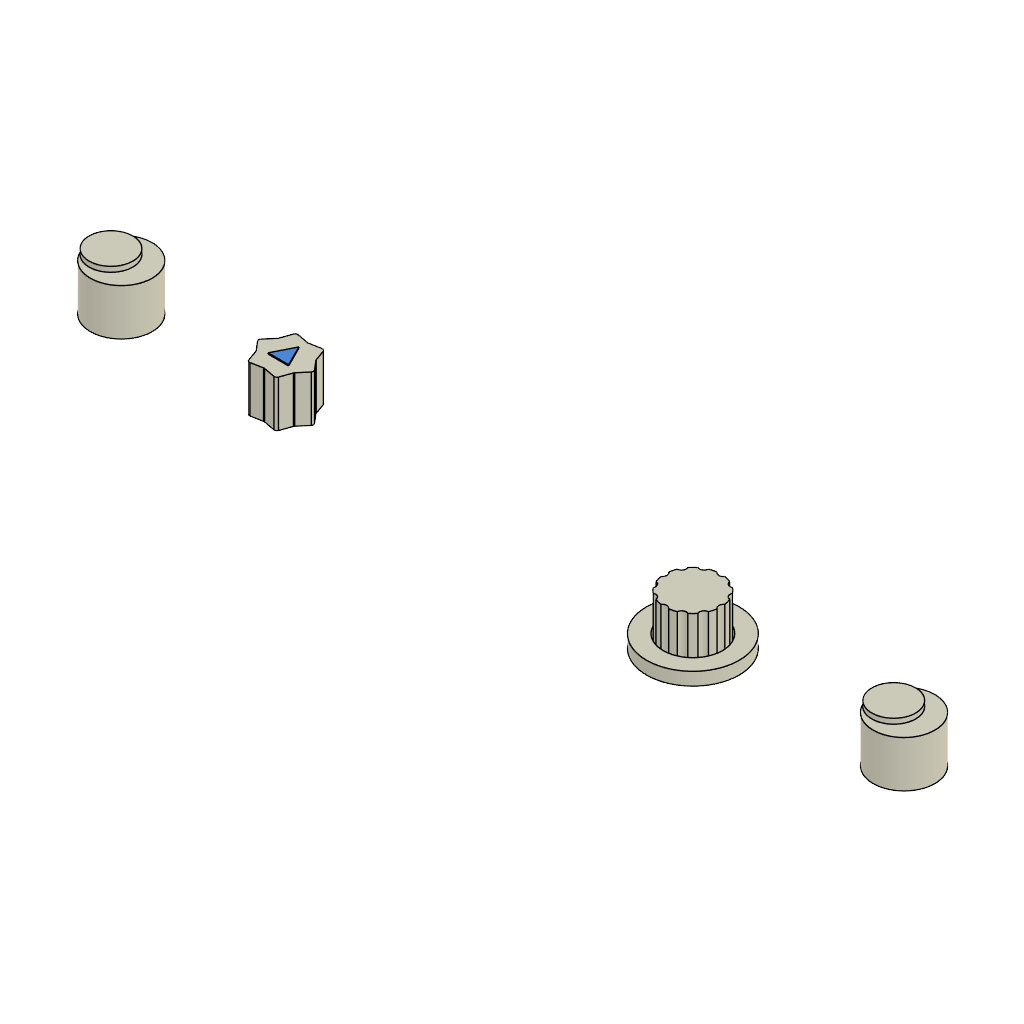
04-printable-fcu-knobs (Autodesk Fusion 360 design; units mm, degrees)
part number: 2026-10-09-16-49-26-165
Autodesk Fusion 360 part; units mm, degrees
ref_plane "WorkPlane1" through (0, 0, 5) normal (0, 0, 1) x (1, 0, 0)
sketch "SPEED knob footprint" plane through (0, 0, 5) normal (0, 0, 1) x (1, 0, 0)
  circle A0 centre (236, 66) radius 12
extrude "SPEED knob" add sketch "SPEED knob footprint" along normal blind 18 makes body 1
ref_plane "WorkPlane2" through (0, 0, 5) normal (0, 0, 1) x (1, 0, 0)
sketch "SPEED shaft socket" plane through (0, 0, 5) normal (0, 0, 1) x (1, 0, 0)
  circle A0 centre (236, 66) radius 3.1
  dimension "d1207" = 6.2
  measures "d1207" diameter of A0
extrude "SPEED shaft socket cut" cut sketch "SPEED shaft socket" along normal blind 14 bodies 1
ref_plane "WorkPlane3" through (0, 0, 23) normal (0, 0, 1) x (1, 0, 0)
sketch "SPEED crown footprint" plane through (0, 0, 23) normal (0, 0, 1) x (1, 0, 0)
  circle A0 centre (232, 66) radius 8.5
extrude "SPEED crown" add sketch "SPEED crown footprint" along normal blind 2 separate body makes body 2
combine "Combine1" operation add target body 1 tool bodies 2
ref_plane "WorkPlane4" through (0, 0, 5) normal (0, 0, 1) x (1, 0, 0)
sketch "Heading lobed knob" plane through (0, 0, 5) normal (0, 0, 1) x (1, 0, 0)
  line L0 (311, 66) -> (307.3612, 70.25)
  line L1 (307.3612, 70.25) -> (305.5, 75.5263)
  line L2 (305.5, 75.5263) -> (300, 74.5)
  line L3 (300, 74.5) -> (294.5, 75.5263)
  line L4 (294.5, 75.5263) -> (292.6388, 70.25)
  line L5 (292.6388, 70.25) -> (289, 66)
  line L6 (289, 66) -> (292.6388, 61.75)
  line L7 (292.6388, 61.75) -> (294.5, 56.4737)
  line L8 (294.5, 56.4737) -> (300, 57.5)
  line L9 (300, 57.5) -> (305.5, 56.4737)
  line L10 (305.5, 56.4737) -> (307.3612, 61.75)
  line L11 (307.3612, 61.75) -> (311, 66)
extrude "HEADING knob" add sketch "Heading lobed knob" along normal blind 18 separate body makes body 3
fillet "Fillet1" radius 1 12 edges at (307.3612, 61.75, 14) (305.5, 56.4737, 14) (300, 57.5, 14) (294.5, 56.4737, 14) (292.6388, 61.75, 14) (289, 66, 14) (292.6388, 70.25, 14) (294.5, 75.5263, 14) (300, 74.5, 14) (305.5, 75.5263, 14) (307.3612, 70.25, 14) (311, 66, 14) on bodies 3
ref_plane "WorkPlane5" through (0, 0, 5) normal (0, 0, 1) x (1, 0, 0)
sketch "HEADING shaft socket" plane through (0, 0, 5) normal (0, 0, 1) x (1, 0, 0)
  circle A0 centre (300, 66) radius 3.1
  dimension "d1222" = 6.2
  measures "d1222" diameter of A0
extrude "HEADING shaft socket cut" cut sketch "HEADING shaft socket" along normal blind 14 bodies 3
ref_plane "WorkPlane6" through (0, 0, 23) normal (0, 0, 1) x (1, 0, 0)
sketch "Heading triangular index" plane through (0, 0, 23) normal (0, 0, 1) x (1, 0, 0)
  line L0 (300, 71) -> (296, 63)
  line L1 (296, 63) -> (304, 63)
  line L2 (304, 63) -> (300, 71)
extrude "Heading triangular index (1)" add sketch "Heading triangular index" along normal blind 0.4 bodies 3
ref_plane "WorkPlane7" through (0, 0, 5) normal (0, 0, 1) x (1, 0, 0)
sketch "ALTITUDE knob footprint" plane through (0, 0, 5) normal (0, 0, 1) x (1, 0, 0)
  circle A0 centre (458, 66) radius 11
extrude "ALTITUDE knob" add sketch "ALTITUDE knob footprint" along normal blind 18 separate body makes body 4
ref_plane "WorkPlane8" through (0, 0, 5) normal (0, 0, 1) x (1, 0, 0)
sketch "ALTITUDE shaft socket" plane through (0, 0, 5) normal (0, 0, 1) x (1, 0, 0)
  circle A0 centre (458, 66) radius 3.1
  dimension "d1235" = 6.2
  measures "d1235" diameter of A0
extrude "ALTITUDE shaft socket cut" cut sketch "ALTITUDE shaft socket" along normal blind 14 bodies 4
ref_plane "WorkPlane9" through (0, 0, 23) normal (0, 0, 1) x (1, 0, 0)
sketch "ALTITUDE grip scallops" plane through (0, 0, 23) normal (0, 0, 1) x (1, 0, 0)
  circle A0 centre (469.9, 66) radius 1.8
  circle A1 centre (468.3057, 71.95) radius 1.8
  circle A2 centre (463.95, 76.3057) radius 1.8
  circle A3 centre (458, 77.9) radius 1.8
  circle A4 centre (452.05, 76.3057) radius 1.8
  circle A5 centre (447.6943, 71.95) radius 1.8
  circle A6 centre (446.1, 66) radius 1.8
  circle A7 centre (447.6943, 60.05) radius 1.8
  circle A8 centre (452.05, 55.6943) radius 1.8
  circle A9 centre (458, 54.1) radius 1.8
  circle A10 centre (463.95, 55.6943) radius 1.8
  circle A11 centre (468.3057, 60.05) radius 1.8
extrude "ALTITUDE grip scallops cut" cut sketch "ALTITUDE grip scallops" against normal blind 18 bodies 4
ref_plane "WorkPlane10" through (0, 0, 5) normal (0, 0, 1) x (1, 0, 0)
sketch "VERTICAL SPEED knob footprint" plane through (0, 0, 5) normal (0, 0, 1) x (1, 0, 0)
  circle A0 centre (540, 66) radius 12
extrude "VERTICAL SPEED knob" add sketch "VERTICAL SPEED knob footprint" along normal blind 18 separate body makes body 5
ref_plane "WorkPlane11" through (0, 0, 5) normal (0, 0, 1) x (1, 0, 0)
sketch "VERTICAL SPEED shaft socket" plane through (0, 0, 5) normal (0, 0, 1) x (1, 0, 0)
  circle A0 centre (540, 66) radius 3.1
  dimension "d1248" = 6.2
  measures "d1248" diameter of A0
extrude "VERTICAL SPEED shaft socket cut" cut sketch "VERTICAL SPEED shaft socket" along normal blind 14 bodies 5
ref_plane "WorkPlane12" through (0, 0, 23) normal (0, 0, 1) x (1, 0, 0)
sketch "VERTICAL SPEED crown footprint" plane through (0, 0, 23) normal (0, 0, 1) x (1, 0, 0)
  circle A0 centre (536, 66) radius 8.5
extrude "VERTICAL SPEED crown" add sketch "VERTICAL SPEED crown footprint" along normal blind 2 separate body makes body 6
combine "Combine2" operation add target body 5 tool bodies 6
ref_plane "WorkPlane13" through (0, 0, 3.5) normal (0, 0, 1) x (1, 0, 0)
sketch "ALTITUDE increment selector collar footprint" plane through (0, 0, 3.5) normal (0, 0, 1) x (1, 0, 0)
  circle A0 centre (458, 66) radius 18
extrude "ALTITUDE increment selector collar" add sketch "ALTITUDE increment selector collar footprint" along normal blind 5 separate body makes body 7
ref_plane "WorkPlane14" through (0, 0, 8.5) normal (0, 0, 1) x (1, 0, 0)
sketch "Altitude collar central clearance" plane through (0, 0, 8.5) normal (0, 0, 1) x (1, 0, 0)
  circle A0 centre (458, 66) radius 11.5
extrude "Altitude collar central clearance cut" cut sketch "Altitude collar central clearance" against normal blind 5 bodies 7
equation "d1207 = shaftBore"
equation "d1222 = shaftBore"
equation "d1235 = shaftBore"
equation "d1248 = shaftBore"
equation "shaftBore = 6.2 mm" comment "Provisional round encoder shaft socket"
named bodies: "SPEED knob", "SPEED crown", "HEADING knob", "ALTITUDE knob", "VERTICAL SPEED knob", "VERTICAL SPEED crown", "ALTITUDE increment selector collar"
